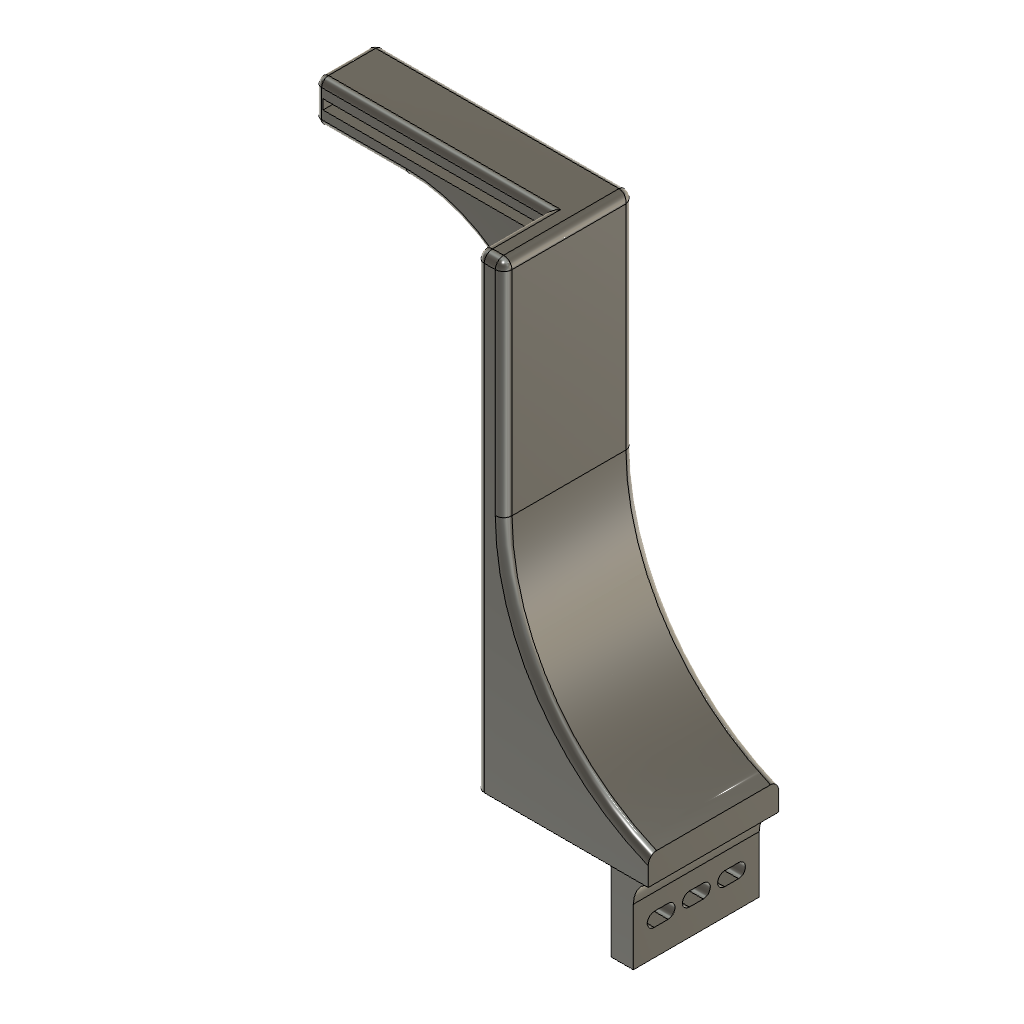
Husky lens connector to conv belt (Autodesk Fusion 360 design; units mm, degrees)
Autodesk Fusion 360 part; units mm, degrees
sketch "Sketch1" plane through (0, 0, 0) normal (1, 0, 0) x (0, 1, 0)
  line L0 (25, -15) -> (-25, -15)
  line L1 (-25, -15) -> (-25, 15)
  line L2 (-25, 15) -> (25, 15)
  line L3 (25, -15) -> (-25, 15) construction
  line L4 (-25, -15) -> (25, 15) construction
  circle A0 centre (-15, -3) radius 2.5
  circle A1 centre (-2.3333, -3) radius 2.5
  circle A2 centre (10.3333, -3) radius 2.5
  line L5 (12.3333, -3) -> (12.3333, -15)
  line L6 (12.3333, 15) -> (-26.6509, 15)
  line L7 (-26.6509, 15) -> (-26.6509, 25)
  line L8 (-26.6509, 25) -> (12.3333, 25)
  line L9 (12.3333, 25) -> (12.3333, 15)
  line L10 (-25, 15) -> (-25, 22)
  line L11 (-15, -3) -> (-25, -3)
  line L12 (-25, -3) -> (12.3333, -3)
  circle A3 centre (-17.5, -3) radius 2.5
  circle A4 centre (-12.5, -3) radius 2.5
  line L13 (-12.5, -3) -> (-12.5, -0.5)
  line L14 (-17.5, -3) -> (-17.5, -0.5)
  line L15 (-17.5, -0.5) -> (-12.5, -0.5)
  line L16 (-12.5, -3) -> (-12.5, -5.5)
  line L17 (-17.5, -3) -> (-17.5, -5.5)
  line L18 (-17.5, -5.5) -> (-12.5, -5.5)
  line L19 (-2.3333, -3) -> (-4.8333, -3)
  circle A5 centre (-4.8333, -3) radius 2.5
  circle A6 centre (0.1667, -3) radius 2.5
  line L20 (-4.8333, -3) -> (-4.8333, -0.5)
  line L21 (-4.8333, -0.5) -> (0.1667, -0.5)
  line L22 (-4.8333, -3) -> (-4.8333, -5.5)
  line L23 (-4.8333, -5.5) -> (0.1667, -5.5)
  circle A7 centre (7.8333, -3) radius 2.5
  circle A8 centre (12.8333, -3) radius 2.5
  line L24 (7.8333, -3) -> (7.8333, -0.5)
  line L25 (7.8333, -0.5) -> (12.8333, -0.5)
  line L26 (7.8333, -3) -> (7.8333, -5.5)
  line L27 (7.8333, -5.5) -> (12.8333, -5.5)
  line L28 (25, -15) -> (12.3333, -15)
  line L29 (12.3333, -15) -> (12.3333, 25)
  line L30 (12.3333, 25) -> (25, 25)
  line L31 (10.3333, -3) -> (20.3333, -3)
  line L32 (20.3333, -3) -> (20.3333, -17)
  line L33 (20.3333, -15) -> (20.3333, 15)
  line L34 (20.3333, 15) -> (20.3333, 25)
  dimension "d1" = 50
  dimension "d2" = 30
  dimension "d3" = 5
  dimension "d4" = 5
  dimension "d5" = 5
  dimension "d6" = 10
  dimension "d7" = 12.6667
  dimension "d8" = 12.6667
  dimension "d9" = 18
  dimension "d10" = 18
  dimension "d12" = 10
  dimension "d13" = 5
  dimension "d14" = 5
  dimension "d15" = 5
  dimension "d16" = 5
  dimension "d17" = 5
  dimension "d18" = 5
  dimension "d19" = 10
  constraint horizontal L0
  constraint perpendicular L0 L1
  constraint parallel L0 L2
  constraint coincident L3 origin
  constraint coincident L4 origin
  constraint coincident L2 L6.start
  constraint coincident L0 L5.end
  constraint perpendicular L0 L5
  constraint horizontal L6
  constraint vertical L7
  constraint horizontal L8
  constraint vertical L9
  constraint perpendicular L8 L10
  constraint coincident A0.centre L11.start
  constraint coincident L1 L11.end
  constraint perpendicular L1 L11
  constraint coincident L11 A3.centre
  constraint coincident A0 A3.centre
  constraint coincident A0 A4.centre
  constraint coincident L12 A4.centre
  constraint coincident A4.centre L13.start
  constraint coincident A4 L13.end
  constraint tangent A0 L13
  constraint perpendicular L12 L13
  constraint coincident A3.centre L14.start
  constraint coincident A3 L14.end
  constraint tangent A0 L14
  constraint perpendicular L11 L14
  constraint coincident A4 L16.end
  constraint tangent A0 L16
  constraint perpendicular L12 L16
  constraint coincident A3 L17.end
  constraint tangent A0 L17
  constraint parallel L14 L17
  constraint coincident A1.centre L19.start
  constraint coincident L12 L19.end
  constraint coincident A1 L19.end
  constraint parallel L12 L19
  constraint coincident L19.end A5.centre
  constraint coincident A1 A6.centre
  constraint coincident L12 A6.centre
  constraint coincident A5 L20.end
  constraint tangent A1 L20
  constraint perpendicular L12 L20
  constraint coincident A6 L21.end
  constraint tangent A6 L21
  constraint coincident A5 L22.end
  constraint tangent A1 L22
  constraint vertical L22
  constraint coincident A6 L23.end
  constraint tangent A6 L23
  constraint coincident A2 A7.centre
  constraint coincident L12 A7.centre
  constraint coincident L12 A8.centre
  constraint coincident A2 A8.centre
  constraint coincident A7.centre L24.start
  constraint coincident A7 L24.end
  constraint tangent A2 L24
  constraint vertical L24
  constraint coincident A8 L25.end
  constraint tangent A8 L25
  constraint coincident A7 L26.end
  constraint tangent A2 L26
  constraint perpendicular L25 L26
  constraint coincident A8 L27.end
  constraint tangent A8 L27
  constraint horizontal L28
  constraint horizontal L30
  constraint coincident A2.centre L31.start
  constraint parallel L12 L31
  constraint perpendicular L0 L32
  constraint coincident L32 L33.start
  constraint coincident L0 L33.start
  constraint coincident L2 L33.end
  constraint perpendicular L2 L33
  constraint coincident L30 L34.end
  constraint perpendicular L30 L34
  measures "d1" distance of L1.end L2.end
  measures "d2" distance of L0.end L1.end
  measures "d3" diameter of A0
  measures "d4" diameter of A1
  measures "d5" diameter of A2
  measures "d6" distance of L1 A0.centre
  measures "d7" distance of A0.centre A1.centre
  measures "d8" horizontal distance of A1.centre A2.centre
  measures "d9" distance of L2 A0.centre
  measures "d10" distance of L2 A2.centre
  measures "d12" distance of L6.start L8.end
  measures "d13" diameter of A3
  measures "d14" diameter of A4
  measures "d15" diameter of A5
  measures "d16" diameter of A6
  measures "d17" diameter of A7
  measures "d18" diameter of A8
  measures "d19" distance of A2.centre L31.end
extrude "Extrude1" add sketch "Sketch1" along normal blind 8 contours L0 L5 A8 L27 L28 L29 L31 L32 L33 | L0 L1 L5 L11 L12 A3 A4 L18 A5 A6 L23 A7 L27 L29 | L2 A8 L25 L29 L31 L33 | L1 L2 L6 L11 L12 A3 A4 L15 A5 A6 L21 A7 L25 L29
extrude "Extrude2" add sketch "Sketch1" along normal blind 15 contours L2 L9 L29 L30 L34 | L2 L6 L7 L8 L9 L29
extrude "Extrude3" add sketch "Sketch1" against normal blind 47 contours L2 L9 L29 L30 L34 | L2 L6 L7 L8 L9 L29
sketch "Sketch2" plane through (0, 0, 25) normal (0, 0, 1) x (-1, 0, 0)
  line L0 (-15, 26.6509) -> (-15, -20.3333)
  line L1 (-15, -20.3333) -> (47, -20.3333)
  line L2 (47, -20.3333) -> (47, 26.6509)
  line L3 (47, 26.6509) -> (37, 26.6509)
  line L4 (37, 26.6509) -> (37, -20.5709)
  line L5 (37, -20.5709) -> (47, -20.5709)
  line L6 (47, -20.5709) -> (47, 26.6509)
  line L7 (47, 26.6509) -> (-15, 26.6509)
  dimension "d26" = 10
  constraint horizontal L3
  constraint vertical L4
  constraint horizontal L5
  constraint vertical L6
  constraint coincident L2.end L3.start
  measures "d26" distance of L2.end L3.end
extrude "Extrude4" add sketch "Sketch2" along normal blind 158 contours L1 L2 L3 L4 L6 L7
fillet "Fillet7" radius 85 1 edges at (-37, -3.1588, 25)
sketch "Sketch4" plane through (-47, 0, 0) normal (-1, 0, 0) x (0, -1, 0)
  line L0 (-20.3333, 15) -> (26.6509, 15)
  line L1 (26.6509, 15) -> (26.6509, 183)
  line L2 (26.6509, 183) -> (-20.3333, 183)
  line L3 (-20.3333, 183) -> (-20.3333, 15)
  line L4 (-20.3333, 183) -> (26.6509, 183)
  line L5 (26.6509, 183) -> (26.6509, 168)
  line L6 (26.6509, 168) -> (-20.3333, 168)
  line L7 (-20.3333, 168) -> (-20.3333, 183)
  dimension "d47" = 15
  constraint horizontal L4
  constraint vertical L5
  constraint horizontal L6
  constraint vertical L7
  constraint coincident L2.end L3.start
  measures "d47" distance of L2.end L6.end
extrude "Extrude6" add sketch "Sketch4" along normal blind 80 contours L1 L2 L3 L4 L5 L6 L7
sketch "Sketch5" plane through (0, -26.6509, 0) normal (0, -1, 0) x (1, 0, 0)
  line L0 (-47, 15) -> (15, 15)
  line L1 (15, 15) -> (15, 25)
  arc A0 (-37, 103.3326) -> (15, 25) centre (48, 103.3326) ccw
  line L2 (-37, 103.3326) -> (-37, 183)
  line L3 (-37, 183) -> (-127, 183)
  line L4 (-127, 183) -> (-127, 168)
  line L5 (-127, 168) -> (-47, 168)
  line L6 (-47, 168) -> (-47, 15)
  line L7 (-127, 175.5) -> (-40, 175.5)
  line L8 (-34.6593, 177.25) -> (-132.3407, 177.25)
  line L9 (-132.3407, 177.25) -> (-132.3407, 173.75)
  line L10 (-132.3407, 173.75) -> (-34.6593, 173.75)
  line L11 (-34.6593, 173.75) -> (-34.6593, 177.25)
  line L12 (-34.6593, 177.25) -> (-132.3407, 173.75) construction
  line L13 (-132.3407, 177.25) -> (-34.6593, 173.75) construction
  line L14 (-47, 168) -> (-47, 183)
  point P0 (-83.5, 175.5)
  dimension "d50" = 3.5
  constraint midpoint L4 L7.start
  constraint perpendicular L4 L7
  constraint horizontal L8
  constraint perpendicular L8 L9
  constraint parallel L8 L10
  constraint parallel L9 L11
  constraint coincident L12 P0
  constraint coincident L13 P0
  constraint midpoint L7 P0
  constraint coincident L5.end L6.start
  constraint coincident L3 L14.end
  constraint perpendicular L3 L14
  measures "d50" distance of L8.end L9.end
extrude "Extrude7" cut sketch "Sketch5" against normal blind 50 contours L4 L7 L10 L14 | L4 L7 L8 L14
extrude "Extrude8" cut sketch "Sketch5" against normal blind 25 contours L4 L5 L10 L14 | L3 L4 L8 L14
sketch "Sketch6" plane through (-127, 0, 0) normal (-1, 0, 0) x (0, -1, 0)
  line L0 (1.6509, 177.25) -> (1.6509, 183)
  line L1 (1.6509, 183) -> (-20.3333, 183)
  line L2 (-20.3333, 183) -> (-20.3333, 177.25)
  line L3 (-20.3333, 177.25) -> (1.6509, 177.25)
  line L4 (-20.3333, 183) -> (1.6509, 183)
  line L5 (1.6509, 183) -> (1.6509, 168)
  line L6 (1.6509, 168) -> (-20.3333, 168)
  line L7 (-20.3333, 168) -> (-20.3333, 183)
  point P0 (1.6509, 168)
  constraint horizontal L4
  constraint vertical L5
  constraint horizontal L6
  constraint vertical L7
  constraint coincident P0 L5.end
  constraint coincident L1.end L2.start
extrude "Extrude9" add sketch "Sketch6" along normal blind 3
fillet "Fillet8" radius 50 1 edges at (-47, 9.3412, 168)
fillet "Fillet9" radius 2.5 11 edges at (-130, 9.3412, 183) (-83.5, 20.3333, 183) (-88.5, -1.6509, 183) (-130, -1.6509, 175.5) (-130, 20.3333, 175.5) (-130, 9.3412, 168) (-61.6447, -1.6509, 153.3553) (-113.5, -1.6509, 168) (-113.5, 20.3333, 168) (-61.6447, 20.3333, 153.3553) (-47, 20.3333, 66.5)
fillet "Fillet10" radius 3 9 edges at (-47, -12.9009, 183) (-42, -26.6509, 183) (-37, -4.4088, 183) (-37, 19.6011, 182.2678) (-37, 20.3333, 141.9163) (-22.8167, 20.3333, 56.322) (-47, -26.6509, 99) (-22.8167, -26.6509, 56.322) (-37, -26.6509, 143.1663)
fillet "Fillet11" radius 10 1 edges at (8, -2.3333, 15)
